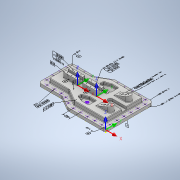
# Autodesk Inventor part: INV_nist_ctc_04_asme1_2021_
Saved by Autodesk Inventor 2021 (Build 250183000, 183)
## iProperties
Created: 2016-11-25
Part Number: INV_nist_ctc_04_asme1_2021_
Material: Generic
Document SubType Name: Modeling
Designer: t_liuje
Density: 1 g/cm^3
Appearance: Default
Author: t_liuje
Autodesk Inventor part; units mm, degrees
ref_plane "YZ Plane" through (0, 0, 0) normal (1, 0, 0) x (0, 1, 0)
sketch "Sketch1" plane through (0, 0, 0) normal (0, 0, 1) x (1, 0, 0)
  line L0 (0, 0) -> (-400.0962, 0)
  line L1 (-780, 75) -> (-780, 425)
  line L2 (-400.0962, 500) -> (0, 500)
  line L3 (0, 500) -> (0, 0)
  line L4 (-400.0962, 500) -> (-530, 425)
  line L5 (-400.0962, 500) -> (-250.0962, 500) construction
  line L6 (-530, 425) -> (-780, 425)
  line L7 (-400.0962, 0) -> (-530, 75)
  line L8 (-530, 75) -> (-780, 75)
  dimension "d5" = 780
  dimension "d10" = 500
  dimension "d11" = 350
  dimension "d12" = 150
  dimension "d13" = 150
  dimension "d14" = 250
  constraints: 18 end point, 4 horizontal, 3 equal length, 2 parallel, 1 perpendicular
  measures "d5" distance between parallel lines of L3 L1
  measures "d10" distance of L2.end L0.start
  measures "d11" distance of L1.start L1.end
  measures "d12" angle of L4 L6
  measures "d13" angle of L8 L7
  measures "d14" distance of L7.end L1.start
extrude "Extrusion1" add sketch "Sketch1" along normal blind 30
sketch "Sketch2" plane through (0, 0, 30) normal (0, 0, 1) x (1, 0, 0)
  line L0 (-780, 425) -> (-780, 75) projected
  line L1 (-780, 75) -> (-530, 75) projected
  line L2 (-530, 75) -> (-400.0962, 0) projected
  line L3 (-400.0962, 0) -> (0, 0) projected
  line L4 (0, 0) -> (0, 500) projected
  line L5 (0, 500) -> (-400.0962, 500) projected
  line L6 (-400.0962, 500) -> (-530, 425) projected
  line L7 (-530, 425) -> (-780, 425) projected
  line L8 (-385.359, 445) -> (-55, 445)
  line L9 (-55, 445) -> (-55, 55)
  line L10 (-55, 55) -> (-385.359, 55)
  line L11 (-385.359, 55) -> (-515.2628, 130)
  line L12 (-515.2628, 130) -> (-725, 130)
  line L13 (-725, 130) -> (-725, 370)
  line L14 (-725, 370) -> (-515.2628, 370)
  line L15 (-515.2628, 370) -> (-385.359, 445)
  dimension "d28" = 55
  constraints: 16 end point, 7 other
  measures "d28" distance between parallel lines of L5 L8
extrude "Extrusion2" add sketch "Sketch2" along normal blind 40 contours L8 L9 L10 L11 L12 L13 L14 L15
sketch "Sketch3" plane through (0, 0, 70) normal (0, 0, 1) x (1, 0, 0)
  line L0 (-655, 290) -> (-505, 290)
  line L1 (-505, 290) -> (-505, 210)
  line L2 (-505, 210) -> (-655, 210)
  line L3 (-655, 210) -> (-655, 290)
  line L4 (-455, 290) -> (-305, 290)
  line L5 (-305, 290) -> (-305, 210)
  line L6 (-305, 210) -> (-455, 210)
  line L7 (-455, 210) -> (-455, 290)
  line L8 (-780, 425) -> (-780, 75) projected
  line L9 (-530, 425) -> (-780, 425) projected
  point P0 (0, 0)
  dimension "d31" = 150
  dimension "d32" = 80
  dimension "d33" = 150
  dimension "d34" = 80
  dimension "d35" = 50
  dimension "d36" = 125
  dimension "d37" = 135
  constraints: 16 end point, 4 parallel, 2 horizontal, 2 perpendicular, 1 collinear
  measures "d31" distance of L1.end L2.end
  measures "d32" distance of L0.end L1.end
  measures "d33" distance of L5.end L6.end
  measures "d34" distance of L4.end L5.end
  measures "d35" distance between parallel lines of L7 L1
  measures "d36" distance between parallel lines of L8 L3
  measures "d37" distance between parallel lines of L0 L9
extrude "Extrusion3" add sketch "Sketch3" along normal blind 50
ref_plane "Work Plane2" through (-225, 0, 70) normal (-0.3746066, 0, 0.9271839) x (0, -1, 0)
sketch "Sketch4" plane through (0, 0, 70) normal (0, 0, 1) x (1, 0, 0)
  line L0 (-225, 375) -> (-105, 375)
  line L1 (-105, 315) -> (-225, 315)
  line L2 (-225, 315) -> (-225, 375)
  line L3 (0, 0) -> (0, 500) projected
  arc A0 (-105, 315) -> (-105, 375) centre (-105, 345) ccw
  line L4 (0, 500) -> (-400.0962, 500) projected
  line L5 (-400.0962, 0) -> (0, 0) projected
  line L6 (-225, 185) -> (-105, 185)
  line L7 (-105, 125) -> (-225, 125)
  line L8 (-225, 125) -> (-225, 185)
  arc A1 (-105, 125) -> (-105, 185) centre (-105, 155) ccw
  dimension "d42" = 60
  dimension "d46" = 225
  dimension "d47" = 120
  dimension "d51" = 125
  dimension "d54" = 60
  dimension "d55" = 120
  dimension "d56" = 125
  dimension "d57" = 225
  constraints: 12 end point, 4 point on circle, 4 tangent, 2 centre point, 2 horizontal, 2 parallel
  measures "d42" distance of L1.end L0.start
  measures "d46" distance between parallel lines of L3 L2
  measures "d47" distance from line of A0.centre L2
  measures "d51" distance between parallel lines of L0 L4
  measures "d54" distance of L7.end L6.start
  measures "d55" distance from line of L8 A1.centre
  measures "d56" distance between parallel lines of L5 L7
  measures "d57" distance between parallel lines of L3 L8
extrude "Extrusion4" add sketch "Sketch4" along normal up to surface surface through (-225, 0, 70) normal (-0.3746066, 0, 0.9271839)
sketch "Sketch5" plane through (0, 0, 70) normal (0, 0, 1) x (1, 0, 0)
  line L0 (-338.059, 171) -> (-273, 171)
  line L1 (-273, 171) -> (-273, 96)
  line L2 (-273, 96) -> (-338.059, 96)
  line L3 (-403, 117.9813) -> (-403, 149.0187)
  line L4 (-338.059, 96) -> (-403, 117.9813)
  line L5 (-338.059, 171) -> (-403, 149.0187)
  line L6 (-385.359, 55) -> (-55, 55) projected
  line L7 (-55, 55) -> (-55, 445) projected
  line L8 (-338.059, 404) -> (-273, 404)
  line L9 (-273, 404) -> (-273, 329)
  line L10 (-273, 329) -> (-338.059, 329)
  line L11 (-403, 350.9813) -> (-403, 382.0187)
  line L12 (-338.059, 329) -> (-403, 350.9813)
  line L13 (-338.059, 404) -> (-403, 382.0187)
  line L14 (-55, 445) -> (-385.359, 445) projected
  point P0 (0, 0)
  dimension "d61" = 75
  dimension "d62" = 161.3
  dimension "d63" = 161.3
  dimension "d64" = 130
  dimension "d65" = 65.059
  dimension "d66" = 41
  dimension "d68" = 75
  dimension "d69" = 161.3
  dimension "d70" = 161.3
  dimension "d71" = 130
  dimension "d72" = 65.059
  dimension "d73" = 218
  dimension "d74" = 218
  dimension "d75" = 41
  constraints: 24 end point, 6 parallel, 2 horizontal, 2 perpendicular
  measures "d61" distance of L0.end L1.end
  measures "d62" angle of L0 L5
  measures "d63" angle of L2 L4
  measures "d64" distance between parallel lines of L1 L3
  measures "d65" distance of L0.start L0.end
  measures "d66" distance between parallel lines of L2 L6
  measures "d68" distance of L8.end L9.end
  measures "d69" angle of L8 L13
  measures "d70" angle of L10 L12
  measures "d71" distance between parallel lines of L9 L11
  measures "d72" distance of L13.start L8.end
  measures "d73" distance between parallel lines of L7 L1
  measures "d74" distance between parallel lines of L7 L9
  measures "d75" distance between parallel lines of L8 L14
extrude "Extrusion5" cut sketch "Sketch5" against normal blind 26.25
fillet "Fillet1" radius 5 30 edges at (-305.5295, 404, 43.75) (-370.5295, 393.0093, 43.75) (-403, 366.5, 43.75) (-370.5295, 339.9907, 43.75) (-305.5295, 329, 43.75) (-273, 366.5, 43.75) (-305.5295, 171, 43.75) (-370.5295, 160.0093, 43.75) (-273, 133.5, 43.75) (-403, 133.5, 43.75) (-370.5295, 106.9907, 43.75) (-305.5295, 96, 43.75) (-273, 96, 56.875) (-338.059, 96, 56.875) (-403, 117.9813, 56.875) (-403, 149.0187, 56.875) (-338.059, 171, 56.875) (-273, 171, 56.875) (-273, 404, 56.875) (-338.059, 404, 56.875) (-273, 329, 56.875) (-338.059, 329, 56.875) (-403, 350.9813, 56.875) (-403, 382.0187, 56.875) (-75, 345, 70) (-165, 375, 70) (-165, 315, 70) (-165, 125, 70) (-165, 185, 70) (-75, 155, 70)
chamfer "Chamfer1" distance 5 angle 45 24 edges at (-307.6179, 404, 70) (-274.4645, 402.5355, 70) (-273, 366.5, 70) (-274.4645, 330.4645, 70) (-307.6179, 329, 70) (-338.0481, 329.0664, 70) (-369.2209, 339.5477, 70) (-402.063, 351.6534, 70) (-403, 366.5, 70) (-402.063, 381.3466, 70) (-369.2209, 393.4523, 70) (-338.0481, 403.9336, 70) (-307.6179, 171, 70) (-274.4645, 169.5355, 70) (-273, 133.5, 70) (-274.4645, 97.4645, 70) (-307.6179, 96, 70) (-338.0481, 96.0664, 70) (-369.2209, 106.5477, 70) (-402.063, 118.6534, 70) (-403, 133.5, 70) (-402.063, 148.3466, 70) (-369.2209, 160.4523, 70) (-338.0481, 170.9336, 70)
fillet "Fillet2" radius 4 16 edges at (-380, 210, 70) (-305, 250, 70) (-505, 250, 70) (-580, 210, 70) (-455, 250, 70) (-655, 250, 70) (-580, 290, 70) (-380, 290, 70) (-505, 210, 95) (-505, 290, 95) (-455, 210, 95) (-305, 210, 95) (-305, 290, 95) (-655, 290, 95) (-655, 210, 95) (-455, 290, 95)
fillet "Fillet8" radius 13 7 edges at (-515.2628, 130, 50) (-385.359, 55, 50) (-725, 130, 50) (-55, 445, 50) (-385.359, 445, 50) (-725, 370, 50) (-55, 55, 50)
fillet "Fillet9" radius 25 8 edges at (-780, 75, 15) (-530, 75, 15) (-400.0962, 0, 15) (0, 0, 15) (0, 500, 15) (-780, 425, 15) (-530, 425, 15) (-400.0962, 500, 15)
fillet "Fillet10" radius 5 30 edges at (-721.1924, 133.8076, 30) (-725, 250, 30) (-721.1924, 366.1924, 30) (-613.6314, 370, 30) (-515.3815, 129.557, 30) (-450.3109, 92.5, 30) (-385.2403, 55.443, 30) (-224.9378, 55, 30) (-58.8076, 58.8076, 30) (-55, 250, 30) (-58.8076, 441.1924, 30) (-224.9378, 445, 30) (-385.2403, 444.557, 30) (-451.8192, 406.6292, 30) (-615.3731, 130, 30) (-515.3815, 129.557, 70) (-450.3109, 92.5, 70) (-385.2403, 55.443, 70) (-224.9378, 55, 70) (-58.8076, 58.8076, 70) (-55, 250, 70) (-58.8076, 441.1924, 70) (-224.9378, 445, 70) (-385.2403, 444.557, 70) (-451.8192, 406.6292, 70) (-721.1924, 133.8076, 70) (-725, 250, 70) (-721.1924, 366.1924, 70) (-613.6314, 370, 70) (-615.3731, 130, 70)
sketch "Sketch6" plane through (0, 0, 70) normal (0, 0, 1) x (1, 0, 0)
  line L0 (-200, 275) -> (-55, 275)
  line L1 (-55, 275) -> (-55, 225)
  line L2 (-55, 225) -> (-200, 225)
  line L3 (-381.8756, 55) -> (-68, 55) projected
  line L4 (-55, 68) -> (-55, 432) projected
  arc A0 (-200, 275) -> (-200, 225) centre (-200, 250) ccw
  point P0 (0, 0)
  dimension "d98" = 170
  dimension "d99" = 145
  dimension "d100" = 50
  constraints: 6 end point, 2 point on circle, 2 tangent, 1 centre point, 1 collinear, 1 horizontal, 1 parallel, 1 perpendicular
  measures "d98" distance between parallel lines of L3 L2
  measures "d99" distance from line of L1 A0.centre
  measures "d100" distance between parallel lines of L2 L0
extrude "Extrusion6" cut sketch "Sketch6" against normal blind 25.125
fillet "Fillet11" radius 2.5 3 edges at (-225, 250, 44.875) (-127.5, 225, 44.875) (-127.5, 275, 44.875)
ref_plane "Work Plane3" through (-393.3975, 250, 0) normal (0, 1, 0) x (1, 0, 0)
sketch "Sketch13" plane through (0, 0, 30) normal (0, 0, 1) x (1, 0, 0)
  point P0 (0, 0)
  point P1 (-20, 215)
  point P2 (-20, 285)
  point P3 (-20, 360)
  point P4 (-20, 435)
  point P5 (-60, 480)
  point P6 (-135, 480)
  point P7 (-210, 480)
  point P8 (-285, 480)
  point P9 (-360, 480)
  point P10 (-435, 456.7543)
  point P11 (-499.9519, 419.2543)
  point P12 (-560, 405)
  point P13 (-635, 405)
  point P14 (-710, 405)
  point P15 (-760, 360)
  point P16 (-760, 285)
  point P17 (-760, 215)
  point P18 (-760, 140)
  point P19 (-710, 95)
  point P20 (-635, 95)
  point P21 (-560, 95)
  point P22 (-499.9519, 80.7457)
  point P23 (-435, 43.2457)
  point P24 (-360, 20)
  point P25 (-285, 20)
  point P26 (-135, 20)
  point P27 (-60, 20)
  point P28 (-20, 65)
  point P29 (-20, 140)
  point P30 (-210, 20)
sketch "Sketch7" plane through (-225, 120, 70) normal (-0.3746066, 0, 0.9271839) x (0.9271839, 0, 0.3746066)
  line L0 (129.4242, 5) -> (13.3473, 5)
  line L1 (129.4242, 255) -> (13.3473, 255)
  point P0 (182.3939, -120)
  point P1 (129.4242, 35)
  point P2 (129.4242, 35)
  point P3 (34.4242, 35)
  point P4 (64.4242, 35)
  point P5 (99.4242, 35)
  point P6 (129.4242, 225)
  point P7 (129.4242, 225)
  point P8 (34.4242, 225)
  point P9 (64.4242, 225)
  point P10 (99.4242, 225)
  dimension "d188" = 95
  dimension "d189" = 30
  dimension "d190" = 30
  dimension "d191" = 35
  constraints: 4 end point, 2 coincident
  measures "d188" distance of point (129.424, 35) point (34.424, 35)
  measures "d189" distance from line of L0 point (34.424, 35)
  measures "d190" distance of point (129.424, 35) point (99.424, 35)
  measures "d191" distance of point (64.424, 35) point (99.424, 35)
sketch "Sketch14" plane through (0, 0, 0) normal (0, 0, -1) x (-1, 0, 0)
  arc A0 (780, 400) -> (755, 425) centre (755, 400) ccw projected
  point P0 (0, 0)
  point P1 (20, 65)
  point P2 (20, 140)
  point P3 (20, 215)
  point P4 (20, 285)
  point P5 (20, 360)
  point P6 (20, 435)
  point P7 (60, 480)
  point P8 (135, 480)
  point P9 (210, 480)
  point P10 (285, 480)
  point P11 (360, 480)
  point P12 (435, 456.7543)
  point P13 (499.9519, 419.2543)
  point P14 (560, 405)
  point P15 (635, 405)
  point P16 (710, 405)
  point P17 (760, 360)
  point P18 (760, 285)
  point P19 (760, 215)
  point P20 (760, 140)
  point P21 (710, 95)
  point P22 (635, 95)
  point P23 (560, 95)
  point P24 (499.9519, 80.7457)
  point P25 (435, 43.2457)
  point P26 (360, 20)
  point P27 (285, 20)
  point P28 (210, 20)
  point P29 (135, 20)
  point P30 (60, 20)
  point P31 (20, 20)
  constraints: 1 coincident
hole "Hole22" at (-755, 400, 0) direction (0, 0, 1) diameter 14 end through all countersink diameter 20 countersink angle 90
hole "Hole8" at (-105, 155, 118.4831) at (-193.0825, 155, 82.8955) at (-193.0825, 345, 82.8955) at (-105, 345, 118.4831) direction (0.3746066, 0, -0.9271839) diameter 10.106 depth 25 tip angle 118 thread size "M12x1.75" class "6H" standard "ANSI Metric M Profile"
hole "Hole10" at (-165.267, 155, 94.1337) at (-132.8155, 155, 107.2449) at (-165.267, 345, 94.1337) at (-132.8155, 345, 107.2449) direction (0.3746066, 0, -0.9271839) diameter 12 depth 40.2 tip angle 118 counterbore diameter 20 counterbore depth 20
hole "Hole20" at (-60, 20, 0) at (-20, 65, 0) at (-20, 140, 0) at (-20, 215, 0) at (-20, 285, 0) at (-20, 360, 0) at (-20, 435, 0) at (-135, 20, 0) at (-210, 20, 0) at (-60, 480, 0) at (-135, 480, 0) at (-210, 480, 0) at (-285, 20, 0) at (-285, 480, 0) at (-360, 480, 0) at (-435, 456.7543, 0) at (-499.9519, 419.2543, 0) at (-560, 405, 0) at (-635, 405, 0) at (-710, 405, 0) at (-760, 360, 0) at (-760, 285, 0) at (-760, 215, 0) at (-760, 140, 0) at (-710, 95, 0) at (-635, 95, 0) at (-560, 95, 0) at (-499.9519, 80.7457, 0) at (-435, 43.2457, 0) at (-360, 20, 0) direction (0, 0, 1) diameter 14 end through all countersink diameter 20 countersink angle 90
hole "Hole21" at (-20, 20, 0) direction (0, 0, 1) diameter 14 end through all countersink diameter 20 countersink angle 90
sketch "Sketch8" plane through (0, 0, 120) normal (0, 0, 1) x (1, 0, 0)
  line L0 (-671.0163, 276.25) -> (-285.0415, 276.25) construction
  line L1 (-671.0163, 223.75) -> (-285.0415, 223.75) construction
  line L2 (-625, 310.9106) -> (-625, 176.517) construction
  line L3 (-580, 310.9106) -> (-580, 176.517) construction
  line L4 (-535, 310.9106) -> (-535, 182.0974) construction
  line L5 (-425, 310.9106) -> (-425, 188.6078) construction
  line L6 (-380, 307.6554) -> (-380, 193.2581) construction
  line L7 (-335, 307.6554) -> (-335, 188.6078) construction
  line L8 (-655, 286) -> (-655, 214) construction
  line L9 (-455, 286) -> (-455, 214) construction
  line L10 (-651, 210) -> (-509, 210) projected
  point P0 (0, 0)
  point P1 (-625, 276.25)
  point P2 (-580, 276.25)
  point P3 (-535, 276.25)
  point P4 (-425, 276.25)
  point P5 (-380, 276.25)
  point P6 (-335, 276.25)
  point P7 (-335, 223.75)
  point P8 (-380, 223.75)
  point P9 (-425, 223.75)
  point P10 (-535, 223.75)
  point P11 (-580, 223.75)
  point P12 (-625, 223.75)
  dimension "d199" = 30
  dimension "d200" = 45
  dimension "d201" = 45
  dimension "d202" = 30
  dimension "d203" = 45
  dimension "d204" = 45
  dimension "d205" = 13.75
  dimension "d206" = 52.5
  constraints: 24 point on line, 16 end point, 6 vertical, 2 horizontal
  measures "d199" distance between parallel lines of L8 L2
  measures "d200" distance between parallel lines of L3 L2
  measures "d201" distance between parallel lines of L4 L3
  measures "d202" distance between parallel lines of L9 L5
  measures "d203" distance between parallel lines of L6 L5
  measures "d204" distance between parallel lines of L7 L6
  measures "d205" distance between parallel lines of L10 L1
  measures "d206" distance between parallel lines of L1 L0
hole "Hole11" at (-625, 276.25, 120) at (-580, 276.25, 120) at (-535, 276.25, 120) at (-535, 223.75, 120) at (-580, 223.75, 120) at (-625, 223.75, 120) direction (0, 0, -1) diameter 6.647 depth 25 tip angle 118
hole "Hole19" at (-425, 276.25, 120) at (-380, 276.25, 120) at (-335, 276.25, 120) at (-335, 223.75, 120) at (-380, 223.75, 120) at (-425, 223.75, 120) direction (0, 0, -1) diameter 6.647 depth 25 tip angle 118
sketch "Sketch9" plane through (-655, 214, 74) normal (-1, 0, 0) x (0, 0, 1)
  line L0 (46, 48.5) -> (21, 48.5)
  line L1 (21, 23.5) -> (46, 23.5)
  line L2 (46, 23.5) -> (46, 48.5)
  line L3 (46, 76) -> (0, 76) projected
  arc A0 (21, 48.5) -> (21, 23.5) centre (21, 36) ccw
  line L4 (46, 72) -> (46, 0) projected
  point P0 (-74, -214)
  dimension "d215" = 25
  dimension "d216" = 27.5
  dimension "d218" = 25
  constraints: 6 end point, 2 point on circle, 2 tangent, 1 centre point, 1 collinear, 1 horizontal, 1 parallel
  measures "d215" distance of L1.start L0.end
  measures "d216" distance between parallel lines of L3 L0
  measures "d218" distance from line of A0.centre L2
extrude "Extrusion7" cut sketch "Sketch9" against normal up to surface (350 mm away)
hole "Hole12" at (-602.5, 210, 108) direction (0, 1, 0) diameter 10 depth 25 tip angle 118
hole "Hole13" at (-402.5, 210, 108) direction (0, 1, 0) diameter 10 depth 25 tip angle 118
sketch "Sketch10" plane through (0, 0, 0) normal (0, 0, -1) x (-1, 0, 0)
  line L0 (25, 0) -> (393.3975, 0) projected
  line L1 (405.8975, 3.3494) -> (524.1987, 71.6506) projected
  line L2 (536.6987, 75) -> (755, 75) projected
  line L3 (780, 100) -> (780, 400) projected
  line L4 (755, 425) -> (536.6987, 425) projected
  line L5 (393.3975, 500) -> (25, 500) projected
  line L6 (524.1987, 428.3494) -> (405.8975, 496.6506) projected
  line L7 (0, 475) -> (0, 25) projected
  line L8 (87.702, 70) -> (379.4037, 70)
  line L9 (491.987, 135) -> (687.702, 135)
  line L10 (87.702, 210) -> (687.702, 210)
  line L11 (87.702, 210) -> (87.702, 70)
  line L12 (687.702, 210) -> (687.702, 135)
  line L13 (379.4037, 70) -> (491.987, 135)
  point P0 (0, 0)
  dimension "d242" = 70
  dimension "d243" = 60
  dimension "d244" = 75
  dimension "d245" = 87.702
  dimension "d246" = 92.298
  dimension "d247" = 70.968
  constraints: 12 end point, 8 point on line, 4 parallel, 2 vertical
  measures "d242" distance between parallel lines of L0 L8
  measures "d243" distance between parallel lines of L2 L9
  measures "d244" distance between parallel lines of L9 L10
  measures "d245" distance between parallel lines of L7 L11
  measures "d246" distance between parallel lines of L3 L12
  measures "d247" distance between parallel lines of L1 L13
extrude "Extrusion8" cut sketch "Sketch10" against normal blind 15.811
fillet "Fillet12" radius 5 12 edges at (-435.6954, 102.5, 15.811) (-589.8445, 135, 15.811) (-687.702, 172.5, 15.811) (-387.702, 210, 15.811) (-687.702, 210, 7.9055) (-687.702, 135, 7.9055) (-491.987, 135, 7.9055) (-379.4037, 70, 7.9055) (-233.5529, 70, 15.811) (-87.702, 70, 7.9055) (-87.702, 140, 15.811) (-87.702, 210, 7.9055)
mirror "Mirror2" about plane through (-393.3975, 250, 0) normal (0, 1, 0) of "Extrusion8", "Fillet12"
sketch "Sketch11" plane through (0, 0, 43.75) normal (0, 0, 1) x (1, 0, 0)
  circle A0 centre (-330.5398, 134.4578) radius 15
  line L0 (-341.1464, 145.0644) -> (-319.9332, 123.8512)
  line L1 (-336.0183, 148.4216) -> (-316.5761, 128.9794)
  line L2 (-328.4185, 149.3071) -> (-315.6906, 136.5792)
  line L3 (-344.5036, 139.9363) -> (-325.0613, 120.4941)
  line L4 (-345.3891, 132.3365) -> (-332.6611, 119.6086)
  constraints: 10 end point, 1 midpoint, 12 other
ref_plane "Work Plane1" through (-225, 0, 0) normal (1, 0, 0) x (0, 0, -1)
equation "\"d13\" = d12"
equation "\"d33\" = d31"
equation "\"d34\" = d32"
equation "\"d54\" = d42"
equation "\"d55\" = d47"
equation "\"d56\" = d51"
equation "\"d57\" = d46"
equation "\"d63\" = d62"
equation "\"d70\" = d69"
equation "\"d74\" = d73"
equation "\"d75\" = d66"
body "Solid1"
